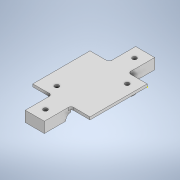
# Autodesk Inventor part: suport_pn532
Saved by Autodesk Inventor 2022.6 (Build 266554000, 554)
## iProperties
Created: 2025-09-23
Part Number: suport_pn532
Material: Generic
Document SubType Name: Modeling
Designer: Dragos Macovei
Density: 1 g/cm^3
Appearance: Default
Author: Dragos Macovei
Autodesk Inventor part; units mm, degrees
ref_plane "YZ Plane" through (0, 0, 0) normal (1, 0, 0) x (0, 1, 0)
ref_plane "XZ Plane" through (0, 0, 0) normal (0, 1, 0) x (-1, 0, 0)
ref_plane "XY Plane" through (0, 0, 0) normal (0, 0, 1) x (1, 0, 0)
sketch "Sketch1" plane through (0, 0, 0) normal (0, 1, 0) x (-1, 0, 0)
  line L0 (0, 0) -> (43, 0)
  line L1 (43, 0) -> (43, 43)
  line L2 (43, 43) -> (0, 43)
  line L3 (0, 43) -> (0, 0)
  dimension "d0" = 43
  dimension "d1" = 43
  constraints: 8 end point, 2 parallel, 1 horizontal, 1 perpendicular
  measures "d0" distance of L2.end L1.end
  measures "d1" distance of L1.end L0.end
extrude "Extrusion1" add sketch "Sketch1" along normal blind 2
sketch "Sketch2" plane through (0, 0, 0) normal (0, -1, 0) x (1, 0, 0)
  line L0 (-43, 0) -> (-43, 43) projected
  line L1 (0, 0) -> (-43, 0) projected
  line L2 (0, 43) -> (0, 0) projected
  line L3 (-43, 43) -> (0, 43) projected
  circle A0 centre (-32.4449, 35.5) radius 1.6
  circle A1 centre (-7.5, 7.5) radius 1.6
  dimension "d4" = 37.5
  dimension "d5" = 3.2
  dimension "d6" = 3.2
  dimension "d7" = 7.5
  dimension "d8" = 7.5
  dimension "d9" = 7.5
  constraints: 2 centre point
  measures "d4" distance of A0.centre A1.centre
  measures "d5" diameter of A1
  measures "d6" diameter of A0
  measures "d7" distance from line of L1 A1.centre
  measures "d8" distance from line of L2 A1.centre
  measures "d9" distance from line of L3 A0.centre
extrude "Extrusion2" cut sketch "Sketch2" against normal blind 2 contours A0 | A1
sketch "Sketch3" plane through (0, 0, 0) normal (0, -1, 0) x (1, 0, 0)
  point P0 (0, 0)
sketch "Sketch4" plane through (0, 0, 0) normal (0, -1, 0) x (1, 0, 0)
  circle A0 centre (-7.5, 7.5) radius 1.6 projected
  circle A1 centre (-32.4449, 35.5) radius 1.6 projected
  line L0 (-43, 0) -> (-43, 43) projected
  line L1 (0, 0) -> (-43, 0) projected
  line L2 (0, 43) -> (0, 0) projected
  line L3 (-43, 43) -> (0, 43) projected
  circle A2 centre (-7.5, 7.5) radius 1.6 projected
  circle A3 centre (-7.5, 7.5) radius 3
  circle A4 centre (-32.4449, 35.5) radius 3
  circle A5 centre (-32.4449, 35.5) radius 5
  circle A6 centre (-7.5, 7.5) radius 5
  dimension "d12" = 6
  dimension "d13" = 6
  dimension "d14" = 10
  dimension "d15" = 10
  constraints: 4 centre point, 4 coincident
  measures "d12" diameter of A3
  measures "d13" diameter of A4
  measures "d14" diameter of A5
  measures "d15" diameter of A6
extrude "Extrusion3" add sketch "Sketch4" along normal blind 3 contours A5 | A6
fillet "Fillet1" radius 2 2 edges at (-37.4449, 0, 35.5) (-12.5, 0, 7.5)
sketch "Sketch5" plane through (0, 2, 0) normal (0, 1, 0) x (1, 0, 0)
  circle A0 centre (-7.5, -7.5) radius 1.6 projected
  circle A1 centre (-32.4449, -35.5) radius 1.6 projected
  line L0 (-43, 0) -> (-43, -43) projected
  line L1 (-43, -43) -> (0, -43) projected
  line L2 (0, -43) -> (0, 0) projected
  line L3 (0, 0) -> (-43, 0) projected
  line L4 (-28.6667, -63) -> (-14.3333, -63)
  line L5 (-14.3333, -63) -> (-14.3333, 20)
  line L6 (-14.3333, 20) -> (-28.6667, 20)
  line L7 (-28.6667, 20) -> (-28.6667, -63)
  point P0 (-21.5, 20)
  point P1 (-28.6667, 0)
  point P2 (-14.3333, 0)
  point P3 (-14.3333, -43)
  point P4 (-28.6667, -43)
  dimension "d19" = 43
  dimension "d20" = 14.3333
  dimension "d21" = 14.3333
  dimension "d22" = 20
  dimension "d23" = 20
  constraints: 8 end point, 2 parallel, 1 horizontal, 1 midpoint, 1 perpendicular
  measures "d19" distance between parallel lines of L2 L0
  measures "d20" distance between parallel lines of L0 L7
  measures "d21" distance between parallel lines of L2 L5
  measures "d22" distance between parallel lines of L1 L4
  measures "d23" distance from line of L3 point (-21.5, 20)
extrude "Extrusion4" add sketch "Sketch5" against normal blind 8 contours L7 L6 L5 L3 | L1 L5 L4 L7
fillet "Fillet2" radius 2 4 edges at (-14.3333, 1, 0) (-14.3333, 1, 43) (-28.6667, 1, 43) (-28.6667, 1, 0)
sketch "Sketch7" plane through (0, 2, 0) normal (0, 1, 0) x (1, 0, 0)
  circle A0 centre (-21.5, 12) radius 1.6
  circle A1 centre (-21.5, -55) radius 1.6
  line L0 (-28.6667, -63) -> (-14.3333, -63) projected
  line L1 (-14.3333, 20) -> (-28.6667, 20) projected
  line L2 (-14.3333, 2) -> (-14.3333, 20) projected
  line L3 (-28.6667, 20) -> (-28.6667, 2) projected
  line L4 (-14.3333, -63) -> (-14.3333, -45) projected
  point P0 (0, 0)
  point P1 (-21.5, -63)
  point P2 (-21.5, 20)
  dimension "d33" = 3.2
  dimension "d34" = 3.2
  dimension "d35" = 8
  dimension "d36" = 8
  dimension "d37" = 14.3333
  dimension "d38" = 7.1667
  dimension "d39" = 7.1667
  constraints: 2 centre point, 2 midpoint
  measures "d33" diameter of A0
  measures "d34" diameter of A1
  measures "d35" distance of point (-21.5, -63) A1.centre
  measures "d36" distance of point (-21.5, 20) A0.centre
  measures "d37" distance between parallel lines of L2 L3
  measures "d38" distance from line of L2 A0.centre
  measures "d39" distance from line of L4 A1.centre
extrude "Extrusion6" cut sketch "Sketch7" against normal blind 10
fillet "Fillet3" radius 4 2 edges at (-21.5, -6, 0) (-21.5, -6, 43) inverted yes
equation "\"d21\" = 0.333333 * d19"
equation "\"d38\" = 0.5 * d37"
equation "\"d39\" = 0.5 * d37"
body "Solid1"
